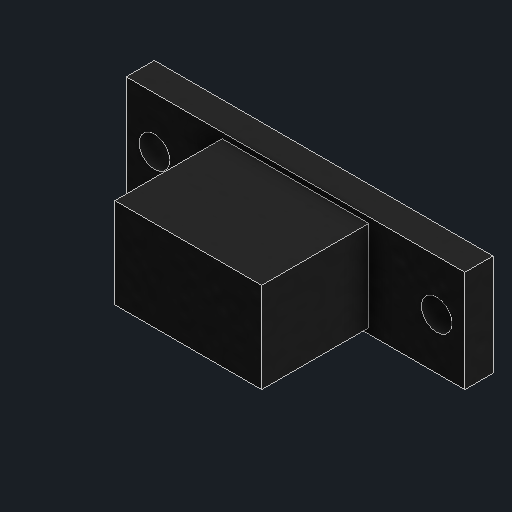
# Autodesk Inventor part: usb_microB_panel_socket
Saved by Autodesk Inventor 2027.1 (Build 311270010, 270A)
## iProperties
Created: 2026-10-29
Part Number: usb_microB_panel_socket
Material: Generic
Document SubType Name: Modeling
Designer: alexg
Density: 1 g/cm^3
Appearance: Black
Author: alexg
Autodesk Inventor part; units mm, degrees
ref_plane "Work Plane1" through (0, 0, -24.8) normal (0, 0, 1) x (1, 0, 0)
sketch "Ear plate sketch" plane through (0, 0, -24.8) normal (0, 0, 1) x (1, 0, 0)
  line L0 (-39, -30.34) -> (-9, -30.34)
  line L1 (-9, -30.34) -> (-9, -21.34)
  line L2 (-9, -21.34) -> (-39, -21.34)
  line L3 (-39, -21.34) -> (-39, -30.34)
  constraints: 8 end point, 2 parallel, 1 horizontal, 1 perpendicular
extrude "Ear plate" add sketch "Ear plate sketch" along normal blind 2.5
ref_plane "Work Plane2" through (0, 0, -22.3) normal (0, 0, 1) x (1, 0, 0)
sketch "Ear holes sketch" plane through (0, 0, -22.3) normal (0, 0, 1) x (1, 0, 0)
  circle A0 centre (-36.5, -25.84) radius 1.35
  circle A1 centre (-11.5, -25.84) radius 1.35
  constraints: 2 centre point
extrude "Ear holes" cut sketch "Ear holes sketch" against normal blind 2.5
ref_plane "Work Plane3" through (0, 0, -24.8) normal (0, 0, 1) x (1, 0, 0)
sketch "Block sketch" plane through (0, 0, -24.8) normal (0, 0, 1) x (1, 0, 0)
  line L0 (-30.5, -29.84) -> (-17.5, -29.84)
  line L1 (-17.5, -29.84) -> (-17.5, -21.84)
  line L2 (-17.5, -21.84) -> (-30.5, -21.84)
  line L3 (-30.5, -21.84) -> (-30.5, -29.84)
  constraints: 8 end point, 2 parallel, 1 horizontal, 1 perpendicular
extrude "Block" add sketch "Block sketch" along normal blind 12
ref_plane "Work Plane4" through (0, 0, -24.8) normal (0, 0, 1) x (1, 0, 0)
sketch "Micro-B opening sketch" plane through (0, 0, -24.8) normal (0, 0, 1) x (1, 0, 0)
  line L0 (-27.75, -27.09) -> (-20.25, -27.09)
  line L1 (-20.25, -27.09) -> (-20.25, -24.59)
  line L2 (-20.25, -24.59) -> (-27.75, -24.59)
  line L3 (-27.75, -24.59) -> (-27.75, -27.09)
  constraints: 8 end point, 2 parallel, 1 horizontal, 1 perpendicular
extrude "Micro-B opening" cut sketch "Micro-B opening sketch" along normal blind 5.8
body "Solid1"
